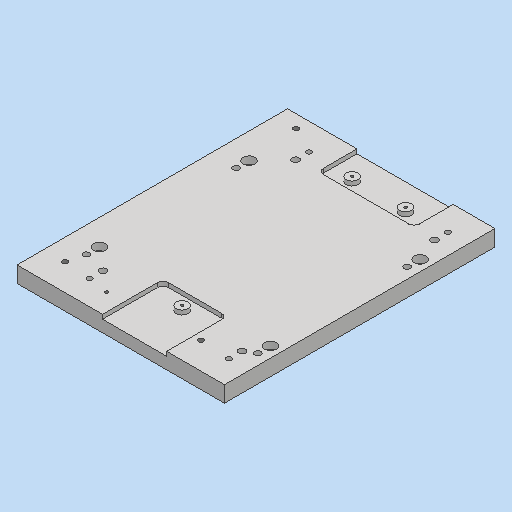
# Autodesk Inventor part: MM0948AN100_G01_101
Saved by Autodesk Inventor 2023.3 (Build 273359000, 359)
## iProperties
Part Number: MM0948AN100_G01_101
Material: 1.2842 90MnCrV8
Description: =<RBPARTNOTITLE2>
Document SubType Name: Modeling
Designer: ric7an
Mass: 5478.7 g
Surface Area: 1191 cm^2
Volume: 697.923 cm^3
Density: 7.85 g/cm^3
Appearance: silber AnP
Created: 2023-03-23
RBDOCUMENTTYPE: DRF
RBDOCUMENTVERSION: 00
RBDRAWINGMAINSCALE: 1:1
RBDRAWINGMISSINGSPEC: --
RBDRAWINGVOLUME: --
RBGBEDGESIN1: +0,5
RBGBEDGESIN2: +0,2
RBGBEDGESOUT1: -0,3
RBGBEDGESOUT2: -0,1
RBMATERIAL: =<Material>
RBMATMEETS: --
RBMATNO: =<Part Number>
RBPARTMADEOF: 15 x 280 x 194 (FM)
RBPARTNO: SIEHE MNR
RBPARTNOTITLE1: manufactured part
RBPARTNOTITLE2: Anfertigungsteil
RBPARTSAFETYINDICATOR: --
RBSURFACE: chemically nickel-coated
RBSURFACE2: chem. vernickelt
RBZEDGESNORM: ISO13715:2002-06
RBZGENDIMCLASS: m
RBZGENDIMNORM: ISO 2768-1:1989-11
RBZGENGEOCLASS: H
RBZGENGEONORM: ISO 2768-2:1989-11
RBZSURFACENORM: ISO13D2:2002-02
RBZTOLERANCENORM: ISO 14405-1:2010-12
AnP_Material: =<Material>
AnP_TemplVers: 20190222
AnP_Kategorie: 1
MaxAbmaße: 15 x 280 x 194 (FM)
AnP_Kommentar_aktuell: =<Comments>
AnP_Material_aktuell: =<Material>
Author: FH/Wi
Keywords: =<RBPARTMADEOF>
Comments: =<RBSURFACE2>
Revision Number: 01
Autodesk Inventor part; units mm, degrees
ref_plane "YZ Plane" through (0, 0, 0) normal (1, 0, 0) x (0, 1, 0)
ref_plane "XZ Plane" through (0, 0, 0) normal (0, 1, 0) x (-1, 0, 0)
ref_plane "XY Plane" through (0, 0, 0) normal (0, 0, 1) x (1, 0, 0)
sketch "Skizze1" plane through (0, 0, 0) normal (0, 0, 1) x (1, 0, 0)
  line L0 (-104, -126.5) -> (90, -126.5)
  line L1 (90, -126.5) -> (90, 126.5)
  line L2 (90, 126.5) -> (-104, 126.5)
  line L3 (-104, 126.5) -> (-104, -126.5)
  line L4 (0, 177.1) -> (0, -177.1) projected
  line L5 (-142.8, 0) -> (128.8, 0) projected
  point P0 (0, 0)
  dimension "d1" = 253
  dimension "d43" = 104
  dimension "d45" = 90
  constraints: 8 end point, 2 parallel, 1 horizontal, 1 perpendicular, 1 other
  measures "d1" distance of L0.end L1.end
  measures "d43" distance between parallel lines of L4 L3
  measures "d45" distance between parallel lines of L1 L4
extrude "Extrusion1" add sketch "Skizze1" along normal blind 15
sketch "Skizze3" plane through (0, 0, 15) normal (0, 0, 1) x (1, 0, 0)
  line L0 (0, 177.1) -> (0, -177.1) projected
  line L1 (-142.8, 0) -> (128.8, 0) projected
  line L2 (-104, -126.5) -> (90, -126.5) projected
  line L3 (-104, 126.5) -> (-104, -126.5) projected
  line L4 (90, -126.5) -> (90, 126.5) projected
  point P0 (0, 0)
  point P1 (-80, 66.5)
  point P2 (-80, -73.5)
  point P3 (80, 66.5)
  point P4 (80, -73.5)
  dimension "d145" = 80
  dimension "d146" = 80
  dimension "d180" = 66.5
  dimension "d181" = 140
  constraints: 2 horizontal alignment, 2 vertical alignment
  measures "d145" horizontal distance of point (0, 0) point (-80, 66.5)
  measures "d146" horizontal distance of point (80, 66.5) point (0, 0)
  measures "d180" distance from line of L1 point (80, 66.5)
  measures "d181" distance of point (80, -73.5) point (80, 66.5)
hole "Bohrung2" at (-80, 66.5, 15) at (-80, -73.5, 15) at (80, 66.5, 15) at (80, -73.5, 15) direction (0, 0, -1) diameter 6.6 end through all counterbore diameter 11 counterbore depth 6.8 clearance for "Inbusschraube ISO 4762  versenkt" size "M6" standard "ISO"
sketch "Skizze4" plane through (0, 0, 0) normal (0, 0, -1) x (-1, 0, 0)
  line L0 (0, -177.1) -> (0, 177.1) projected
  line L1 (-128.8, 0) -> (142.8, 0) projected
  line L2 (-90, -126.5) -> (-90, 126.5) projected
  line L3 (-90, 126.5) -> (104, 126.5) projected
  point P0 (0, 0)
  point P1 (-71, 89)
  point P2 (59, 89)
  point P3 (59, -91)
  point P4 (-71, -91)
  dimension "d25" = 180
  dimension "d48" = 130
  dimension "d135" = 37.5
  dimension "d192" = 59
  constraints: 2 horizontal alignment, 2 vertical alignment
  measures "d25" distance of point (59, -91) point (59, 89)
  measures "d48" distance of point (59, -91) point (-71, -91)
  measures "d135" distance from line of point (59, 89) L3
  measures "d192" distance from line of L0 point (59, -91)
hole "Bohrung3" at (71, 89, 0) at (-59, 89, 0) at (-59, -91, 0) at (71, -91, 0) direction (0, 0, 1) diameter 6.6 end through all counterbore diameter 11 counterbore depth 6.8 clearance for "Inbusschraube ISO 4762  versenkt" size "M6" standard "ISO"
sketch "Skizze8" plane through (0, 0, 15) normal (0, 0, 1) x (1, 0, 0)
  line L0 (90, 126.5) -> (-104, 126.5) projected
  line L1 (90, -126.5) -> (90, 126.5) projected
  point P0 (0, 0)
  point P1 (30.95, 102)
  point P2 (-19.05, 102)
  point P3 (5.95, -82)
  dimension "d62" = 50
  dimension "d63" = 184
  dimension "d64" = 25
  dimension "d65" = 24.5
  dimension "d144" = 30.95
  constraints: 1 horizontal alignment
  measures "d62" distance of point (-19.05, 102) point (30.95, 102)
  measures "d63" vertical distance of point (30.95, 102) point (5.95, -82)
  measures "d64" horizontal distance of point (30.95, 102) point (5.95, -82)
  measures "d65" distance from line of L0 point (30.95, 102)
  measures "d144" horizontal distance of point (30.95, 102) point (0, 0)
hole "Bohrung5" at (30.95, 102, 15) at (-19.05, 102, 15) at (5.95, -82, 15) direction (0, 0, -1) diameter 2.459 end through all thread size "M3x0.5" designation "M3" class "6H" standard "ISO Metric profile"
sketch "Skizze9" plane through (0, 0, 15) normal (0, 0, 1) x (1, 0, 0)
  circle A0 centre (71, 89) radius 3.3 projected
  circle A1 centre (-59, 89) radius 3.3 projected
  circle A2 centre (71, -91) radius 3.3 projected
  point P0 (0, 0)
  point P1 (71, 101.5)
  point P2 (71, -103.5)
  point P3 (-59, -103.5)
  point P4 (-59, 101.5)
  dimension "d75" = 12.5
  dimension "d136" = 12.5
  constraints: 4 vertical alignment, 2 horizontal alignment
  measures "d75" distance of point (71, 101.5) A0.centre
  measures "d136" distance of point (71, -103.5) A2.centre
hole "Bohrung6" at (71, 101.5, 15) at (71, -103.5, 15) at (-59, -103.5, 15) at (-59, 101.5, 15) direction (0, 0, -1) diameter 5 end through all
sketch "Skizze11" plane through (0, 0, 15) normal (0, 0, 1) x (1, 0, 0)
  circle A0 centre (-80, 66.5) radius 5.5 projected
  circle A1 centre (-80, -73.5) radius 5.5 projected
  circle A2 centre (80, -73.5) radius 5.5 projected
  circle A3 centre (80, 66.5) radius 5.5 projected
  point P0 (0, 0)
  point P1 (-80, 54.5)
  point P2 (-80, -85.5)
  point P3 (80, -85.5)
  point P4 (80, 54.5)
  dimension "d88" = 12
  dimension "d147" = 12
  constraints: 4 vertical alignment, 2 horizontal alignment
  measures "d88" distance of point (80, -85.5) A2.centre
  measures "d147" distance of point (80, 54.5) A3.centre
hole "Bohrung7" at (-80, 54.5, 15) at (-80, -85.5, 15) at (80, -85.5, 15) at (80, 54.5, 15) direction (0, 0, -1) diameter 6 end through all
sketch "Skizze13" plane through (0, 0, 15) normal (0, 0, 1) x (1, 0, 0)
  line L0 (-39.05, 126.5) -> (50.95, 126.5)
  line L1 (50.95, 126.5) -> (50.95, 90)
  line L2 (50.95, 90) -> (-39.05, 90)
  line L3 (-39.05, 90) -> (-39.05, 126.5)
  circle A0 centre (71, 101.5) radius 2.5 projected
  circle A1 centre (-19.05, 102) radius 1.2295 projected
  circle A2 centre (30.95, 102) radius 1.2295 projected
  circle A3 centre (71, 89) radius 3.3 projected
  circle A4 centre (-19.05, 102) radius 5.5
  circle A5 centre (30.95, 102) radius 5.5
  circle A6 centre (5.95, -82) radius 5.5
  line L4 (-24.05, -126.5) -> (35.95, -126.5)
  line L5 (35.95, -126.5) -> (35.95, -70)
  line L6 (35.95, -70) -> (-24.05, -70)
  line L7 (-24.05, -70) -> (-24.05, -126.5)
  circle A7 centre (5.95, -82) radius 1.2295 projected
  line L8 (90, 126.5) -> (-104, 126.5) projected
  line L9 (-104, -126.5) -> (90, -126.5) projected
  point P0 (0, 0)
  point P1 (5.95, -70)
  dimension "d104" = 11
  dimension "d105" = 11
  dimension "d106" = 11
  dimension "d108" = 20
  dimension "d109" = 20
  dimension "d111" = 30
  dimension "d178" = 12
  dimension "d179" = 12
  constraints: 16 end point, 7 centre point, 4 parallel, 3 coincident, 2 horizontal, 2 perpendicular, 1 collinear, 1 midpoint, 1 point on line, 1 vertical alignment
  measures "d104" diameter of A4
  measures "d105" diameter of A5
  measures "d106" diameter of A6
  measures "d108" distance from line of L1 A2.centre
  measures "d109" distance from line of A1.centre L3
  measures "d111" distance from line of L5 A6.centre
  measures "d178" distance from line of L2 A1.centre
  measures "d179" distance from line of A7.centre L6
extrude "Extrusion5" cut sketch "Skizze13" against normal blind 4 contours L0 L1 L2 L3 | L7 L6 L5 L4
fillet "Rundung2" radius 5 4 edges at (50.95, 90, 13) (-39.05, 90, 13) (-24.05, -70, 13) (35.95, -70, 13)
sketch "Skizze16" plane through (0, 0, 15) normal (0, 0, 1) x (1, 0, 0)
  line L0 (-104, 126.5) -> (-104, -126.5) projected
  line L1 (90, 126.5) -> (-104, 126.5) projected
  line L2 (-104, -126.5) -> (90, -126.5) projected
  line L3 (90, -126.5) -> (90, 126.5) projected
  point P0 (0, 0)
  point P1 (-84, 114.5)
  point P2 (-84, -101.5)
  point P3 (43, -101.5)
  point P4 (-7, 126.5)
  dimension "d155" = 20
  dimension "d156" = 12
  dimension "d157" = 20
  dimension "d159" = 47
  dimension "d182" = 228
  constraints: 1 horizontal alignment, 1 midpoint
  measures "d155" distance from line of point (-84, 114.5) L0
  measures "d156" distance from line of point (-84, 114.5) L1
  measures "d157" distance from line of point (-84, -101.5) L0
  measures "d159" distance from line of L3 point (43, -101.5)
  measures "d182" vertical distance of point (-7, 126.5) point (-84, -101.5)
hole "Bohrung9" at (-84, 114.5, 15) at (-84, -101.5, 15) at (43, -101.5, 15) direction (0, 0, -1) diameter 4.917 end through all thread size "M6x1" designation "M6" class "6H" standard "ISO Metric profile"
sketch "Skizze17" plane through (-104, 126.5, 0) normal (0, 1, 0) x (1, 0, 0)
  line L0 (194, 0) -> (0, 0) projected
  line L1 (104, 0) -> (104, -12.9062)
  point P0 (172, -7.5)
  point P1 (48, -7.5)
  dimension "d168" = 7.5
  dimension "d169" = 124
  dimension "d193" = 68
  constraints: 2 end point, 1 vertical
  measures "d168" distance from line of point (172, -7.5) L0
  measures "d169" distance of point (172, -7.5) point (48, -7.5)
  measures "d193" distance from line of L1 point (172, -7.5)
hole "Bohrung10" at (68, 126.5, 7.5) at (-56, 126.5, 7.5) direction (0, -1, 0) diameter 4.917 depth 17.1 tip angle 118 thread size "M6x1" designation "M6" class "6H" standard "ISO Metric profile"
sketch "Skizze18" plane through (-104, 126.5, 0) normal (0, 1, 0) x (1, 0, 0)
  circle A0 centre (48, -7.5) radius 2.4585 projected
  circle A1 centre (172, -7.5) radius 2.4585 projected
  line L0 (48, -7.5) -> (60, -7.5)
  line L1 (60, -7.5) -> (160, -7.5) construction
  line L2 (160, -7.5) -> (172, -7.5)
  point P0 (104, 0)
  dimension "d177" = 12
  constraints: 6 end point, 2 coincident, 2 collinear, 1 horizontal, 1 point on line
  measures "d177" distance of L0.start L0.end
hole "Bohrung11" at (56, 126.5, 7.5) at (-44, 126.5, 7.5) direction (0, -1, 0) diameter 6 depth 12 tip angle 118
sketch "Skizze19" plane through (0, 0, 15) normal (0, 0, 1) x (1, 0, 0)
  line L0 (-104, 126.5) -> (-104, -126.5) projected
  line L1 (-104, -126.5) -> (-24.05, -126.5) projected
  point P0 (0, 0)
  point P1 (-40, -106.5)
  dimension "d183" = 64
  dimension "d184" = 20
  measures "d183" distance from line of point (-40, -106.5) L0
  measures "d184" distance from line of L1 point (-40, -106.5)
hole "Bohrung12" at (-40, -106.5, 15) direction (0, 0, -1) diameter 2.85 end through all thread size "M3.5x0.6" designation "M3.5" class "6H" standard "ISO Metric profile"
equation "\"d109\" = d108"
